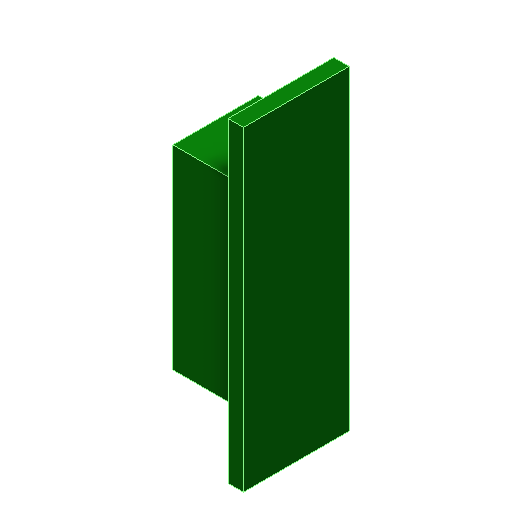
# Autodesk Inventor part: REF - OT2-Pipette V0.3 - identity board + 2x5 header
Saved by Autodesk Inventor 2025.5 (Build 295498000, 498)
## iProperties
Created: 2026-11-01
Part Number: REF - OT2-Pipette V0.3 - identity board + 2x5 header
Material: Generisch
Description: identity board placeholder: perfboard with the shrouded 2x5 header through the wall
Document SubType Name: Modeling
Designer: benir
Density: 1 g/cm^3
Appearance: Dark Green
Author: benir
Autodesk Inventor part; units mm, degrees
ref_plane "XZ Plane" through (0, 0, 0) normal (0, 1, 0) x (-1, 0, 0)
ref_plane "x=wall_x1" through (-2.2, 0, 0) normal (1, 0, 0) x (0, 1, 0)
sketch "board" plane through (-2.2, 0, 0) normal (1, 0, 0) x (0, 1, 0)
  line L0 (59.55, 7.5) -> (92.45, 7.5)
  line L1 (92.45, 7.5) -> (92.45, 18.5)
  line L2 (92.45, 18.5) -> (59.55, 18.5)
  line L3 (59.55, 18.5) -> (59.55, 7.5)
  line L4 (0, -3.7) -> (0, 22.2) projected
  line L5 (-18.49, 0) -> (110.94, 0) projected
  point P0 (0, 0)
  dimension "d3" = 32.9
  dimension "d4" = 11
  dimension "d5" = 59.55
  dimension "d6" = 7.5
  constraints: 8 end point, 2 parallel, 1 horizontal, 1 perpendicular
  measures "d3" distance of L0.start L0.end
  measures "d4" distance of L2.end L0.start
  measures "d5" horizontal distance of point (0, 0) L2.end
  measures "d6" vertical distance of point (0, 0) L0.start
extrude "perfboard" add sketch "board" along normal blind 1.6
ref_plane "x=mount_x + hdr_in" through (-9, 0, 0) normal (1, 0, 0) x (0, 1, 0)
sketch "header" plane through (-9, 0, 0) normal (1, 0, 0) x (0, 1, 0)
  line L0 (65.85, 8.55) -> (86.15, 8.55)
  line L1 (86.15, 8.55) -> (86.15, 17.45)
  line L2 (86.15, 17.45) -> (65.85, 17.45)
  line L3 (65.85, 17.45) -> (65.85, 8.55)
  line L4 (0, -3.7) -> (0, 22.2) projected
  line L5 (-18.49, 0) -> (110.94, 0) projected
  point P0 (0, 0)
  dimension "d10" = 20.3
  dimension "d11" = 8.9
  dimension "d12" = 65.85
  dimension "d13" = 8.55
  constraints: 8 end point, 2 parallel, 1 horizontal, 1 perpendicular
  measures "d10" distance of L0.start L0.end
  measures "d11" distance of L2.end L0.start
  measures "d12" horizontal distance of point (0, 0) L2.end
  measures "d13" vertical distance of point (0, 0) L0.start
extrude "2x5 shrouded header" add sketch "header" along normal blind 6.8
equation "\"d3\" = pcb_margin + hdr_y + 0.5 * hdr_l - pcb_y0"
equation "\"d4\" = pcb_z1 + pcb_hw - hdr_z"
equation "\"d5\" = pcb_y0"
equation "\"d6\" = hdr_z - pcb_hw"
equation "\"d7\" = pcb_t"
equation "\"d10\" = hdr_body_l + 0 * hdr_y"
equation "\"d11\" = hdr_body_w + 0 * hdr_z"
equation "\"d12\" = hdr_y - 0.5 * hdr_body_l"
equation "\"d13\" = hdr_z - 0.5 * hdr_body_w"
equation "\"d14\" = -mount_x + wall_x1 - hdr_in"
equation "\"pcb_margin\" = 6"
equation "\"hdr_y\" = 76"
equation "\"hdr_l\" = 20.9"
equation "\"pcb_y0\" = 59.55"
equation "\"pcb_z1\" = 18.5"
equation "\"pcb_hw\" = 5.5"
equation "\"hdr_z\" = 13"
equation "\"pcb_t\" = 1.6"
equation "\"hdr_body_l\" = 20.3"
equation "\"hdr_body_w\" = 8.9"
equation "\"mount_x\" = -9.5"
equation "\"wall_x1\" = -2.2"
equation "\"hdr_in\" = 0.5"
body "Solid2"
